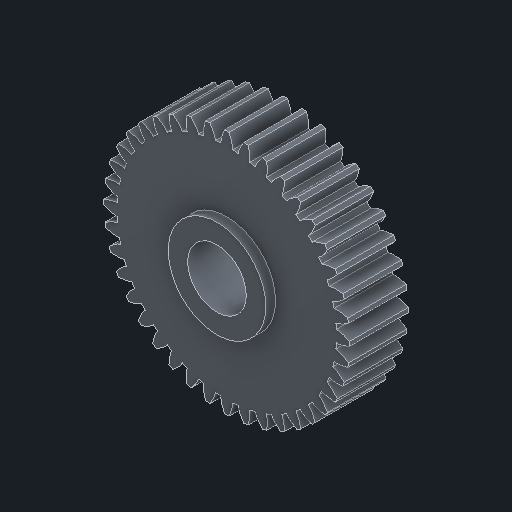
# Autodesk Inventor part: G2
Saved by Autodesk Inventor 2027 (Build 310192000, 192)
## iProperties
Created: 2026-11-10
Part Number: G2
Material: Genérico
Description: Engrenagem G2
Document SubType Name: Modeling
Designer: Bruno Madela
Mass: 40.9588 g
Surface Area: 123.761 cm^2
Volume: 40.9588 cm^3
Density: 1 g/cm^3
Appearance: Aço
Author: Bruno Madela
Autodesk Inventor part; units mm, degrees
(part 1 of 2)
ref_plane "YZ Plane" through (0, 0, 0) normal (1, 0, 0) x (0, 1, 0)
ref_plane "XZ Plane" through (0, 0, 0) normal (0, 1, 0) x (-1, 0, 0)
sketch "Esboço1" plane through (0, 0, 0) normal (0, 0, 1) x (1, 0, 0)
  circle A0 centre (0, 0) radius 12.5
  dimension "d0" = 25
  constraints: 1 centre point
  measures "d0" diameter of A0
extrude "Extrusão1" add sketch "Esboço1" along normal blind 20
ref_plane "Plano de trabalho1" through (0, 0, 2.5) normal (0, 0, 1) x (1, 0, 0)
sketch "Esboço2" plane through (0, 0, 2.5) normal (0, 0, 1) x (1, 0, 0)
  spline S0 degree 4 poles (28.0837, -1.5229) (28.1193, -1.5226) (28.1898, -1.5213) (28.2932, -1.5177) (28.4266, -1.5092) (28.5556, -1.4973) (28.6808, -1.4819) (28.8029, -1.4634) (28.9231, -1.4421) (29.0426, -1.4185) (29.1623, -1.3927) (29.2827, -1.3651) (29.4038, -1.3357) (29.525, -1.3045) (29.6461, -1.2716) (29.7667, -1.237) (29.887, -1.2007) (30.0069, -1.1627) (30.1267, -1.1233) (30.2466, -1.0824) (30.3664, -1.04) (30.486, -0.9963) (30.6056, -0.9511) (30.7248, -0.9046) (30.8438, -0.8568) (30.9626, -0.8076) (31.0812, -0.7571) (31.1996, -0.7054) (31.3178, -0.6525) (31.4064, -0.6118) (31.4654, -0.5843) (31.4948, -0.5705) knots 0 0 0 0 0 0.035714 0.071429 0.107143 0.142857 0.178571 0.214286 0.25 0.285714 0.321429 0.357143 0.392857 0.428571 0.464286 0.5 0.535714 0.571429 0.607143 0.642857 0.678571 0.714286 0.75 0.785714 0.821429 0.857143 0.892857 0.928571 0.964286 1 1 1 1 1
  spline S1 degree 4 poles (31.4948, 0.5705) (31.4653, 0.5845) (31.4062, 0.6123) (31.3175, 0.6534) (31.1991, 0.707) (31.0805, 0.7593) (30.9617, 0.8102) (30.8428, 0.8599) (30.7236, 0.9082) (30.6042, 0.9551) (30.4846, 1.0006) (30.3648, 1.0447) (30.2449, 1.0873) (30.125, 1.1284) (30.0051, 1.1681) (29.8851, 1.2062) (29.7648, 1.2427) (29.6441, 1.2774) (29.523, 1.3103) (29.4018, 1.3414) (29.2807, 1.3707) (29.1602, 1.3983) (29.0405, 1.424) (28.9209, 1.4477) (28.8007, 1.4688) (28.6787, 1.487) (28.5537, 1.5019) (28.425, 1.513) (28.2921, 1.5202) (28.1892, 1.5227) (28.1191, 1.5231) (28.0837, 1.5229) knots 0 0 0 0 0 0.035714 0.071429 0.107143 0.142857 0.178571 0.214286 0.25 0.285714 0.321429 0.357143 0.392857 0.428571 0.464286 0.5 0.535714 0.571429 0.607143 0.642857 0.678571 0.714286 0.75 0.785714 0.821429 0.857143 0.892857 0.928571 0.964286 1 1 1 1 1
  spline S2 degree 4 poles (27.9762, 2.8891) (28.0112, 2.8945) (28.0802, 2.9059) (28.1813, 2.9245) (28.3113, 2.9526) (28.4365, 2.9838) (28.5575, 3.0181) (28.6751, 3.0553) (28.7905, 3.0951) (28.9048, 3.1372) (29.019, 3.1815) (29.1336, 3.2276) (29.2486, 3.2756) (29.3635, 3.3253) (29.4779, 3.3767) (29.5917, 3.4299) (29.7048, 3.4847) (29.8174, 3.5411) (29.9296, 3.599) (30.0417, 3.6583) (30.1535, 3.7191) (30.265, 3.7813) (30.3761, 3.8449) (30.4867, 3.9099) (30.597, 3.9761) (30.7068, 4.0437) (30.8162, 4.1125) (30.9253, 4.1826) (31.034, 4.2539) (31.1152, 4.3083) (31.1693, 4.345) (31.1963, 4.3634) knots 0 0 0 0 0 0.035714 0.071429 0.107143 0.142857 0.178571 0.214286 0.25 0.285714 0.321429 0.357143 0.392857 0.428571 0.464286 0.5 0.535714 0.571429 0.607143 0.642857 0.678571 0.714286 0.75 0.785714 0.821429 0.857143 0.892857 0.928571 0.964286 1 1 1 1 1
  spline S3 degree 4 poles (31.0178, 5.4903) (30.9865, 5.4996) (30.9238, 5.5178) (30.8297, 5.5446) (30.7044, 5.579) (30.5791, 5.6121) (30.4538, 5.6439) (30.3285, 5.6743) (30.2033, 5.7034) (30.078, 5.7311) (29.9527, 5.7573) (29.8275, 5.7821) (29.7024, 5.8055) (29.5775, 5.8274) (29.4529, 5.8478) (29.3284, 5.8667) (29.2039, 5.8839) (29.0793, 5.8993) (28.9545, 5.9128) (28.8299, 5.9246) (28.7057, 5.9346) (28.5824, 5.943) (28.4601, 5.9497) (28.3383, 5.9543) (28.2163, 5.9564) (28.0929, 5.9553) (27.9672, 5.9503) (27.8383, 5.9411) (27.706, 5.9275) (27.6039, 5.9138) (27.5347, 5.9031) (27.4997, 5.8974) knots 0 0 0 0 0 0.035714 0.071429 0.107143 0.142857 0.178571 0.214286 0.25 0.285714 0.321429 0.357143 0.392857 0.428571 0.464286 0.5 0.535714 0.571429 0.607143 0.642857 0.678571 0.714286 0.75 0.785714 0.821429 0.857143 0.892857 0.928571 0.964286 1 1 1 1 1
  spline S4 degree 4 poles (27.1798, 7.23) (27.2135, 7.2408) (27.28, 7.2627) (27.377, 7.2969) (27.5011, 7.3448) (27.6199, 7.3952) (27.7341, 7.4479) (27.8445, 7.503) (27.9523, 7.5603) (28.0586, 7.6197) (28.1645, 7.6813) (28.2705, 7.7447) (28.3766, 7.8101) (28.4823, 7.8771) (28.5873, 7.9459) (28.6913, 8.0162) (28.7945, 8.088) (28.8968, 8.1613) (28.9986, 8.2361) (29.1, 8.3123) (29.2009, 8.3899) (29.3012, 8.4688) (29.401, 8.549) (29.5001, 8.6305) (29.5986, 8.7132) (29.6964, 8.7972) (29.7937, 8.8824) (29.8904, 8.9687) (29.9865, 9.0562) (30.0582, 9.1227) (30.1059, 9.1674) (30.1297, 9.1899) knots 0 0 0 0 0 0.035714 0.071429 0.107143 0.142857 0.178571 0.214286 0.25 0.285714 0.321429 0.357143 0.392857 0.428571 0.464286 0.5 0.535714 0.571429 0.607143 0.642857 0.678571 0.714286 0.75 0.785714 0.821429 0.857143 0.892857 0.928571 0.964286 1 1 1 1 1
  spline S5 degree 4 poles (29.7771, 10.275) (29.7447, 10.2792) (29.6799, 10.2874) (29.5829, 10.2991) (29.4537, 10.3135) (29.3248, 10.3266) (29.1961, 10.3383) (29.0677, 10.3488) (28.9394, 10.3579) (28.8114, 10.3657) (28.6836, 10.372) (28.556, 10.3769) (28.4289, 10.3804) (28.3021, 10.3825) (28.1758, 10.3831) (28.0499, 10.3823) (27.9243, 10.3798) (27.7988, 10.3755) (27.6734, 10.3694) (27.5485, 10.3615) (27.4243, 10.352) (27.3012, 10.341) (27.1794, 10.3284) (27.0584, 10.3139) (26.9376, 10.2969) (26.8159, 10.2764) (26.6925, 10.2519) (26.5666, 10.2227) (26.4379, 10.1885) (26.3391, 10.1591) (26.2723, 10.1378) (26.2386, 10.1267) knots 0 0 0 0 0 0.035714 0.071429 0.107143 0.142857 0.178571 0.214286 0.25 0.285714 0.321429 0.357143 0.392857 0.428571 0.464286 0.5 0.535714 0.571429 0.607143 0.642857 0.678571 0.714286 0.75 0.785714 0.821429 0.857143 0.892857 0.928571 0.964286 1 1 1 1 1
  spline S6 degree 4 poles (25.7142, 11.3928) (25.7458, 11.4088) (25.808, 11.4409) (25.8984, 11.4898) (26.0134, 11.5566) (26.1229, 11.625) (26.2274, 11.695) (26.3278, 11.7667) (26.4252, 11.8402) (26.521, 11.9156) (26.616, 11.9929) (26.7107, 12.0722) (26.8053, 12.1533) (26.8992, 12.2361) (26.9921, 12.3204) (27.0839, 12.4061) (27.1745, 12.4932) (27.2642, 12.5817) (27.353, 12.6714) (27.4412, 12.7625) (27.5287, 12.8549) (27.6155, 12.9485) (27.7015, 13.0433) (27.7867, 13.1393) (27.871, 13.2364) (27.9545, 13.3346) (28.0373, 13.4339) (28.1193, 13.5343) (28.2006, 13.6357) (28.2611, 13.7126) (28.3011, 13.7642) (28.3211, 13.7901) knots 0 0 0 0 0 0.035714 0.071429 0.107143 0.142857 0.178571 0.214286 0.25 0.285714 0.321429 0.357143 0.392857 0.428571 0.464286 0.5 0.535714 0.571429 0.607143 0.642857 0.678571 0.714286 0.75 0.785714 0.821429 0.857143 0.892857 0.928571 0.964286 1 1 1 1 1
  spline S7 degree 4 poles (27.8031, 14.8066) (27.7704, 14.8057) (27.7052, 14.8037) (27.6075, 14.8001) (27.4776, 14.7941) (27.3482, 14.7868) (27.2193, 14.7783) (27.0907, 14.7685) (26.9626, 14.7575) (26.8349, 14.7451) (26.7077, 14.7313) (26.581, 14.7162) (26.4548, 14.6998) (26.3293, 14.682) (26.2044, 14.6629) (26.0802, 14.6424) (25.9565, 14.6202) (25.8332, 14.5964) (25.7104, 14.5707) (25.5882, 14.5434) (25.467, 14.5146) (25.3471, 14.4845) (25.2287, 14.453) (25.1115, 14.4198) (24.9947, 14.3841) (24.8777, 14.3449) (24.7596, 14.3013) (24.6399, 14.2528) (24.5183, 14.1989) (24.4255, 14.1544) (24.3629, 14.1229) (24.3314, 14.1067) knots 0 0 0 0 0 0.035714 0.071429 0.107143 0.142857 0.178571 0.214286 0.25 0.285714 0.321429 0.357143 0.392857 0.428571 0.464286 0.5 0.535714 0.571429 0.607143 0.642857 0.678571 0.714286 0.75 0.785714 0.821429 0.857143 0.892857 0.928571 0.964286 1 1 1 1 1
  spline S8 degree 4 poles (23.6154, 15.2751) (23.6441, 15.2958) (23.7005, 15.3372) (23.7823, 15.3997) (23.8855, 15.4836) (23.983, 15.5682) (24.0754, 15.6536) (24.1634, 15.7401) (24.2482, 15.8279) (24.331, 15.9173) (24.4127, 16.0086) (24.4939, 16.1017) (24.5746, 16.1966) (24.6545, 16.2931) (24.7331, 16.3909) (24.8103, 16.4899) (24.8862, 16.5901) (24.9609, 16.6914) (25.0346, 16.794) (25.1074, 16.8978) (25.1794, 17.0027) (25.2504, 17.1088) (25.3205, 17.2159) (25.3895, 17.3241) (25.4576, 17.4332) (25.5246, 17.5433) (25.5908, 17.6544) (25.6561, 17.7664) (25.7204, 17.8793) (25.7681, 17.9647) (25.7995, 18.022) (25.8152, 18.0507) knots 0 0 0 0 0 0.035714 0.071429 0.107143 0.142857 0.178571 0.214286 0.25 0.285714 0.321429 0.357143 0.392857 0.428571 0.464286 0.5 0.535714 0.571429 0.607143 0.642857 0.678571 0.714286 0.75 0.785714 0.821429 0.857143 0.892857 0.928571 0.964286 1 1 1 1 1
  spline S9 degree 4 poles (25.1445, 18.9737) (25.1124, 18.9677) (25.0483, 18.9555) (24.9524, 18.9366) (24.8252, 18.9102) (24.6986, 18.8828) (24.5726, 18.8542) (24.4472, 18.8244) (24.3224, 18.7934) (24.1983, 18.7611) (24.0748, 18.7276) (23.952, 18.6928) (23.83, 18.6568) (23.7088, 18.6196) (23.5885, 18.5812) (23.4691, 18.5414) (23.3503, 18.5002) (23.2323, 18.4574) (23.115, 18.4128) (22.9986, 18.3667) (22.8834, 18.3193) (22.7697, 18.2708) (22.6577, 18.2212) (22.547, 18.1701) (22.4373, 18.1166) (22.3278, 18.0596) (22.218, 17.9982) (22.1072, 17.9316) (21.9954, 17.8594) (21.9106, 17.801) (21.8537, 17.7602) (21.8251, 17.7393) knots 0 0 0 0 0 0.035714 0.071429 0.107143 0.142857 0.178571 0.214286 0.25 0.285714 0.321429 0.357143 0.392857 0.428571 0.464286 0.5 0.535714 0.571429 0.607143 0.642857 0.678571 0.714286 0.75 0.785714 0.821429 0.857143 0.892857 0.928571 0.964286 1 1 1 1 1
  spline S10 degree 4 poles (20.9351, 18.7813) (20.9601, 18.8063) (21.0093, 18.856) (21.0802, 18.9305) (21.1688, 19.0296) (21.2517, 19.1285) (21.3295, 19.2273) (21.4027, 19.3265) (21.4726, 19.4265) (21.5403, 19.5278) (21.6067, 19.6307) (21.6723, 19.7354) (21.7371, 19.8418) (21.8009, 19.9495) (21.8632, 20.0584) (21.924, 20.1683) (21.9833, 20.2791) (22.0412, 20.3909) (22.098, 20.5038) (22.1538, 20.6177) (22.2085, 20.7326) (22.2621, 20.8484) (22.3147, 20.9652) (22.366, 21.0828) (22.4163, 21.2012) (22.4654, 21.3204) (22.5135, 21.4404) (22.5606, 21.5612) (22.6066, 21.6828) (22.6404, 21.7746) (22.6626, 21.836) (22.6736, 21.8668) knots 0 0 0 0 0 0.035714 0.071429 0.107143 0.142857 0.178571 0.214286 0.25 0.285714 0.321429 0.357143 0.392857 0.428571 0.464286 0.5 0.535714 0.571429 0.607143 0.642857 0.678571 0.714286 0.75 0.785714 0.821429 0.857143 0.892857 0.928571 0.964286 1 1 1 1 1
  spline S11 degree 4 poles (21.8668, 22.6736) (21.836, 22.6626) (21.7745, 22.6405) (21.6827, 22.6069) (21.5611, 22.5611) (21.4403, 22.5142) (21.3202, 22.4662) (21.201, 22.4173) (21.0825, 22.3672) (20.9649, 22.3159) (20.8482, 22.2635) (20.7323, 22.21) (20.6174, 22.1553) (20.5035, 22.0997) (20.3906, 22.0429) (20.2788, 21.985) (20.168, 21.9257) (20.0581, 21.865) (19.9492, 21.8026) (19.8414, 21.7388) (19.7351, 21.674) (19.6304, 21.6083) (19.5275, 21.5418) (19.4262, 21.474) (19.3263, 21.4039) (19.2271, 21.3305) (19.1283, 21.2526) (19.0295, 21.1694) (18.9304, 21.0806) (18.856, 21.0095) (18.8062, 20.9602) (18.7813, 20.9351) knots 0 0 0 0 0 0.035714 0.071429 0.107143 0.142857 0.178571 0.214286 0.25 0.285714 0.321429 0.357143 0.392857 0.428571 0.464286 0.5 0.535714 0.571429 0.607143 0.642857 0.678571 0.714286 0.75 0.785714 0.821429 0.857143 0.892857 0.928571 0.964286 1 1 1 1 1
  spline S12 degree 4 poles (17.7393, 21.8251) (17.7602, 21.8536) (17.801, 21.9105) (17.8595, 21.9952) (17.9316, 22.1069) (17.9982, 22.2175) (18.0596, 22.3274) (18.1165, 22.4368) (18.17, 22.5465) (18.2211, 22.6572) (18.2707, 22.7692) (18.3191, 22.8829) (18.3665, 22.9981) (18.4126, 23.1145) (18.4572, 23.2318) (18.5, 23.3498) (18.5413, 23.4686) (18.581, 23.5881) (18.6194, 23.7084) (18.6566, 23.8296) (18.6926, 23.9516) (18.7274, 24.0744) (18.761, 24.1979) (18.7932, 24.3221) (18.8243, 24.4469) (18.8541, 24.5723) (18.8827, 24.6984) (18.9102, 24.825) (18.9365, 24.9523) (18.9554, 25.0482) (18.9677, 25.1124) (18.9737, 25.1445) knots 0 0 0 0 0 0.035714 0.071429 0.107143 0.142857 0.178571 0.214286 0.25 0.285714 0.321429 0.357143 0.392857 0.428571 0.464286 0.5 0.535714 0.571429 0.607143 0.642857 0.678571 0.714286 0.75 0.785714 0.821429 0.857143 0.892857 0.928571 0.964286 1 1 1 1 1
  spline S13 degree 4 poles (18.0507, 25.8152) (18.022, 25.7995) (17.9647, 25.7681) (17.8793, 25.7205) (17.7664, 25.6562) (17.6544, 25.591) (17.5434, 25.5249) (17.4333, 25.4578) (17.3242, 25.3898) (17.216, 25.3208) (17.1089, 25.2508) (17.0029, 25.1798) (16.8979, 25.1078) (16.7942, 25.035) (16.6916, 24.9613) (16.5902, 24.8866) (16.49, 24.8107) (16.391, 24.7335) (16.2932, 24.6549) (16.1968, 24.5751) (16.1019, 24.4944) (16.0087, 24.4131) (15.9175, 24.3313) (15.8281, 24.2485) (15.7403, 24.1637) (15.6538, 24.0756) (15.5684, 23.9832) (15.4837, 23.8856) (15.3998, 23.7824) (15.3373, 23.7006) (15.2958, 23.6441) (15.2751, 23.6154) knots 0 0 0 0 0 0.035714 0.071429 0.107143 0.142857 0.178571 0.214286 0.25 0.285714 0.321429 0.357143 0.392857 0.428571 0.464286 0.5 0.535714 0.571429 0.607143 0.642857 0.678571 0.714286 0.75 0.785714 0.821429 0.857143 0.892857 0.928571 0.964286 1 1 1 1 1
  spline S14 degree 4 poles (14.1067, 24.3314) (14.1229, 24.3628) (14.1544, 24.4254) (14.199, 24.5181) (14.2529, 24.6397) (14.3014, 24.7594) (14.345, 24.8774) (14.3841, 24.9944) (14.4199, 25.1111) (14.453, 25.2284) (14.4845, 25.3468) (14.5146, 25.4667) (14.5434, 25.5879) (14.5708, 25.71) (14.5964, 25.8329) (14.6203, 25.9562) (14.6424, 26.0799) (14.6629, 26.2041) (14.682, 26.329) (14.6998, 26.4545) (14.7162, 26.5807) (14.7313, 26.7075) (14.7451, 26.8347) (14.7575, 26.9624) (14.7686, 27.0906) (14.7783, 27.2191) (14.7868, 27.3481) (14.7941, 27.4775) (14.8001, 27.6074) (14.8037, 27.7051) (14.8057, 27.7704) (14.8066, 27.8031) knots 0 0 0 0 0 0.035714 0.071429 0.107143 0.142857 0.178571 0.214286 0.25 0.285714 0.321429 0.357143 0.392857 0.428571 0.464286 0.5 0.535714 0.571429 0.607143 0.642857 0.678571 0.714286 0.75 0.785714 0.821429 0.857143 0.892857 0.928571 0.964286 1 1 1 1 1
  spline S15 degree 4 poles (13.7901, 28.3211) (13.7642, 28.3011) (13.7126, 28.2611) (13.6357, 28.2008) (13.5342, 28.1196) (13.4338, 28.0377) (13.3345, 27.955) (13.2363, 27.8716) (13.1392, 27.7873) (13.0432, 27.7022) (12.9483, 27.6163) (12.8547, 27.5296) (12.7623, 27.4421) (12.6712, 27.354) (12.5814, 27.2651) (12.493, 27.1755) (12.4059, 27.0849) (12.3202, 26.9931) (12.2359, 26.9002) (12.1531, 26.8062) (12.072, 26.7117) (11.9928, 26.6169) (11.9154, 26.5218) (11.8401, 26.426) (11.7666, 26.3285) (11.695, 26.228) (11.625, 26.1233) (11.5567, 26.0137) (11.4899, 25.8986) (11.4409, 25.8081) (11.4088, 25.7458) (11.3928, 25.7142) knots 0 0 0 0 0 0.035714 0.071429 0.107143 0.142857 0.178571 0.214286 0.25 0.285714 0.321429 0.357143 0.392857 0.428571 0.464286 0.5 0.535714 0.571429 0.607143 0.642857 0.678571 0.714286 0.75 0.785714 0.821429 0.857143 0.892857 0.928571 0.964286 1 1 1 1 1
  spline S16 degree 4 poles (10.1267, 26.2386) (10.1378, 26.2722) (10.1592, 26.3389) (10.1887, 26.4375) (10.2228, 26.566) (10.2521, 26.6918) (10.2766, 26.8153) (10.297, 26.937) (10.314, 27.0578) (10.3284, 27.1788) (10.341, 27.3007) (10.352, 27.4238) (10.3615, 27.548) (10.3694, 27.673) (10.3755, 27.7983) (10.3798, 27.9238) (10.3822, 28.0495) (10.3831, 28.1754) (10.3824, 28.3017) (10.3803, 28.4285) (10.3768, 28.5557) (10.3719, 28.6832) (10.3656, 28.8111) (10.3579, 28.9391) (10.3488, 29.0674) (10.3383, 29.1959) (10.3265, 29.3246) (10.3135, 29.4536) (10.2991, 29.5828) (10.2874, 29.6799) (10.2792, 29.7447) (10.275, 29.7771) knots 0 0 0 0 0 0.035714 0.071429 0.107143 0.142857 0.178571 0.214286 0.25 0.285714 0.321429 0.357143 0.392857 0.428571 0.464286 0.5 0.535714 0.571429 0.607143 0.642857 0.678571 0.714286 0.75 0.785714 0.821429 0.857143 0.892857 0.928571 0.964286 1 1 1 1 1
  spline S17 degree 4 poles (9.1899, 30.1297) (9.1674, 30.1059) (9.1226, 30.0583) (9.0561, 29.9867) (8.9685, 29.8906) (8.8821, 29.794) (8.7968, 29.6968) (8.7128, 29.5991) (8.63, 29.5007) (8.5484, 29.4016) (8.4681, 29.3019) (8.3892, 29.2016) (8.3116, 29.1008) (8.2354, 28.9995) (8.1606, 28.8977) (8.0872, 28.7953) (8.0154, 28.6922) (7.945, 28.5881) (7.8763, 28.4832) (7.8093, 28.3774) (7.744, 28.2713) (7.6805, 28.1653) (7.619, 28.0593) (7.5596, 27.9529) (7.5024, 27.8451) (7.4474, 27.7346) (7.3947, 27.6203) (7.3445, 27.5013) (7.2967, 27.3772) (7.2626, 27.2801) (7.2407, 27.2135) (7.23, 27.1798) knots 0 0 0 0 0 0.035714 0.071429 0.107143 0.142857 0.178571 0.214286 0.25 0.285714 0.321429 0.357143 0.392857 0.428571 0.464286 0.5 0.535714 0.571429 0.607143 0.642857 0.678571 0.714286 0.75 0.785714 0.821429 0.857143 0.892857 0.928571 0.964286 1 1 1 1 1
  spline S18 degree 4 poles (5.8974, 27.4997) (5.9031, 27.5347) (5.9138, 27.6039) (5.9275, 27.7059) (5.9412, 27.8382) (5.9504, 27.967) (5.9553, 28.0927) (5.9565, 28.2161) (5.9544, 28.3382) (5.9497, 28.4599) (5.943, 28.5823) (5.9346, 28.7056) (5.9246, 28.8297) (5.9128, 28.9544) (5.8993, 29.0791) (5.8839, 29.2038) (5.8667, 29.3283) (5.8478, 29.4528) (5.8274, 29.5774) (5.8055, 29.7023) (5.7821, 29.8274) (5.7573, 29.9526) (5.7311, 30.0779) (5.7034, 30.2032) (5.6743, 30.3284) (5.6439, 30.4537) (5.6121, 30.579) (5.579, 30.7043) (5.5446, 30.8297) (5.5178, 30.9238) (5.4996, 30.9865) (5.4903, 31.0178) knots 0 0 0 0 0 0.035714 0.071429 0.107143 0.142857 0.178571 0.214286 0.25 0.285714 0.321429 0.357143 0.392857 0.428571 0.464286 0.5 0.535714 0.571429 0.607143 0.642857 0.678571 0.714286 0.75 0.785714 0.821429 0.857143 0.892857 0.928571 0.964286 1 1 1 1 1
  spline S19 degree 4 poles (4.3634, 31.1963) (4.3449, 31.1694) (4.3082, 31.1154) (4.2536, 31.0342) (4.1822, 30.9256) (4.112, 30.8167) (4.043, 30.7073) (3.9753, 30.5976) (3.9089, 30.4875) (3.8439, 30.3769) (3.7802, 30.2659) (3.7179, 30.1545) (3.657, 30.0427) (3.5976, 29.9307) (3.5396, 29.8185) (3.4832, 29.7059) (3.4284, 29.5928) (3.3752, 29.4791) (3.3238, 29.3646) (3.2741, 29.2497) (3.2262, 29.1347) (3.1801, 29.0201) (3.1359, 28.9058) (3.0939, 28.7914) (3.0542, 28.6759) (3.0172, 28.5582) (2.983, 28.4371) (2.952, 28.3117) (2.9241, 28.1816) (2.9057, 28.0804) (2.8945, 28.0112) (2.8891, 27.9762) knots 0 0 0 0 0 0.035714 0.071429 0.107143 0.142857 0.178571 0.214286 0.25 0.285714 0.321429 0.357143 0.392857 0.428571 0.464286 0.5 0.535714 0.571429 0.607143 0.642857 0.678571 0.714286 0.75 0.785714 0.821429 0.857143 0.892857 0.928571 0.964286 1 1 1 1 1
  spline S20 degree 4 poles (1.5229, 28.0837) (1.5231, 28.1191) (1.5229, 28.1892) (1.5205, 28.292) (1.5134, 28.4249) (1.5024, 28.5535) (1.4877, 28.6785) (1.4695, 28.8006) (1.4484, 28.9208) (1.4247, 29.0403) (1.399, 29.1601) (1.3715, 29.2806) (1.3421, 29.4017) (1.311, 29.523) (1.2781, 29.644) (1.2434, 29.7647) (1.2069, 29.885) (1.1688, 30.005) (1.1291, 30.1249) (1.0879, 30.2448) (1.0453, 30.3647) (1.0012, 30.4845) (0.9556, 30.6042) (0.9087, 30.7236) (0.8603, 30.8427) (0.8106, 30.9617) (0.7595, 31.0805) (0.7072, 31.1991) (0.6536, 31.3175) (0.6124, 31.4062) (0.5845, 31.4653) (0.5705, 31.4948) knots 0 0 0 0 0 0.035714 0.071429 0.107143 0.142857 0.178571 0.214286 0.25 0.285714 0.321429 0.357143 0.392857 0.428571 0.464286 0.5 0.535714 0.571429 0.607143 0.642857 0.678571 0.714286 0.75 0.785714 0.821429 0.857143 0.892857 0.928571 0.964286 1 1 1 1 1
  spline S21 degree 4 poles (-0.5705, 31.4948) (-0.5845, 31.4653) (-0.6124, 31.4062) (-0.6536, 31.3175) (-0.7072, 31.1991) (-0.7596, 31.0805) (-0.8106, 30.9617) (-0.8603, 30.8428) (-0.9087, 30.7236) (-0.9557, 30.6042) (-1.0012, 30.4846) (-1.0453, 30.3648) (-1.088, 30.2449) (-1.1292, 30.125) (-1.1689, 30.0051) (-1.207, 29.8851) (-1.2435, 29.7648) (-1.2782, 29.6441) (-1.3111, 29.523) (-1.3422, 29.4017) (-1.3715, 29.2807) (-1.3991, 29.1602) (-1.4248, 29.0404) (-1.4484, 28.9208) (-1.4695, 28.8006) (-1.4877, 28.6786) (-1.5024, 28.5536) (-1.5134, 28.4249) (-1.5205, 28.2921) (-1.5229, 28.1892) (-1.5231, 28.1191) (-1.5229, 28.0837) knots 0 0 0 0 0 0.035714 0.071429 0.107143 0.142857 0.178571 0.214286 0.25 0.285714 0.321429 0.357143 0.392857 0.428571 0.464286 0.5 0.535714 0.571429 0.607143 0.642857 0.678571 0.714286 0.75 0.785714 0.821429 0.857143 0.892857 0.928571 0.964286 1 1 1 1 1
  spline S22 degree 4 poles (-2.8891, 27.9762) (-2.8944, 28.0112) (-2.9056, 28.0803) (-2.924, 28.1816) (-2.9518, 28.3117) (-2.9828, 28.437) (-3.0169, 28.5582) (-3.0539, 28.6759) (-3.0936, 28.7913) (-3.1356, 28.9057) (-3.1798, 29.02) (-3.2258, 29.1347) (-3.2737, 29.2496) (-3.3234, 29.3646) (-3.3749, 29.479) (-3.4281, 29.5928) (-3.4829, 29.7059) (-3.5393, 29.8184) (-3.5973, 29.9307) (-3.6567, 30.0427) (-3.7176, 30.1544) (-3.7799, 30.2658) (-3.8436, 30.3769) (-3.9087, 30.4875) (-3.9751, 30.5976) (-4.0428, 30.7073) (-4.1118, 30.8166) (-4.1821, 30.9256) (-4.2536, 31.0342) (-4.3082, 31.1154) (-4.3449, 31.1694) (-4.3634, 31.1963) knots 0 0 0 0 0 0.035714 0.071429 0.107143 0.142857 0.178571 0.214286 0.25 0.285714 0.321429 0.357143 0.392857 0.428571 0.464286 0.5 0.535714 0.571429 0.607143 0.642857 0.678571 0.714286 0.75 0.785714 0.821429 0.857143 0.892857 0.928571 0.964286 1 1 1 1 1
  spline S23 degree 4 poles (-5.4903, 31.0178) (-5.4996, 30.9865) (-5.5179, 30.9238) (-5.5447, 30.8297) (-5.5791, 30.7043) (-5.6122, 30.579) (-5.644, 30.4537) (-5.6745, 30.3285) (-5.7036, 30.2032) (-5.7313, 30.0779) (-5.7576, 29.9526) (-5.7824, 29.8274) (-5.8058, 29.7023) (-5.8277, 29.5775) (-5.8482, 29.4528) (-5.867, 29.3283) (-5.8842, 29.2038) (-5.8997, 29.0792) (-5.9132, 28.9544) (-5.925, 28.8298) (-5.935, 28.7056) (-5.9434, 28.5823) (-5.95, 28.46) (-5.9547, 28.3382) (-5.9567, 28.2161) (-5.9556, 28.0927) (-5.9506, 27.967) (-5.9414, 27.8382) (-5.9276, 27.7059) (-5.9139, 27.6039) (-5.9032, 27.5347) (-5.8974, 27.4997) knots 0 0 0 0 0 0.035714 0.071429 0.107143 0.142857 0.178571 0.214286 0.25 0.285714 0.321429 0.357143 0.392857 0.428571 0.464286 0.5 0.535714 0.571429 0.607143 0.642857 0.678571 0.714286 0.75 0.785714 0.821429 0.857143 0.892857 0.928571 0.964286 1 1 1 1 1
  spline S24 degree 4 poles (-7.23, 27.1798) (-7.2407, 27.2135) (-7.2626, 27.2801) (-7.2966, 27.3772) (-7.3444, 27.5013) (-7.3946, 27.6203) (-7.4472, 27.7346) (-7.5022, 27.8451) (-7.5595, 27.9529) (-7.6189, 28.0593) (-7.6804, 28.1652) (-7.7438, 28.2713) (-7.8091, 28.3774) (-7.8762, 28.4831) (-7.9449, 28.5881) (-8.0152, 28.6921) (-8.0871, 28.7953) (-8.1604, 28.8976) (-8.2352, 28.9994) (-8.3114, 29.1007) (-8.3891, 29.2016) (-8.468, 29.3019) (-8.5483, 29.4016) (-8.6299, 29.5006) (-8.7127, 29.599) (-8.7968, 29.6968) (-8.882, 29.794) (-8.9684, 29.8906) (-9.056, 29.9867) (-9.1226, 30.0583) (-9.1674, 30.1059) (-9.1899, 30.1297) knots 0 0 0 0 0 0.035714 0.071429 0.107143 0.142857 0.178571 0.214286 0.25 0.285714 0.321429 0.357143 0.392857 0.428571 0.464286 0.5 0.535714 0.571429 0.607143 0.642857 0.678571 0.714286 0.75 0.785714 0.821429 0.857143 0.892857 0.928571 0.964286 1 1 1 1 1
  spline S25 degree 4 poles (-10.275, 29.7771) (-10.2792, 29.7447) (-10.2875, 29.6798) (-10.2993, 29.5828) (-10.3137, 29.4535) (-10.3268, 29.3246) (-10.3387, 29.1959) (-10.3492, 29.0674) (-10.3584, 28.9391) (-10.3662, 28.811) (-10.3726, 28.6832) (-10.3775, 28.5556) (-10.381, 28.4284) (-10.3832, 28.3016) (-10.3839, 28.1753) (-10.383, 28.0494) (-10.3806, 27.9237) (-10.3763, 27.7982) (-10.3702, 27.6729) (-10.3623, 27.5479) (-10.3527, 27.4237) (-10.3417, 27.3006) (-10.3292, 27.1788) (-10.3147, 27.0577) (-10.2976, 26.9369) (-10.2771, 26.8152) (-10.2525, 26.6918) (-10.2232, 26.566) (-10.1889, 26.4375) (-10.1593, 26.3389) (-10.1379, 26.2722) (-10.1267, 26.2386) knots 0 0 0 0 0 0.035714 0.071429 0.107143 0.142857 0.178571 0.214286 0.25 0.285714 0.321429 0.357143 0.392857 0.428571 0.464286 0.5 0.535714 0.571429 0.607143 0.642857 0.678571 0.714286 0.75 0.785714 0.821429 0.857143 0.892857 0.928571 0.964286 1 1 1 1 1
  spline S26 degree 4 poles (-11.3928, 25.7142) (-11.4087, 25.7458) (-11.4407, 25.8081) (-11.4895, 25.8987) (-11.5561, 26.0138) (-11.6243, 26.1235) (-11.6941, 26.2282) (-11.7657, 26.3287) (-11.8391, 26.4262) (-11.9144, 26.522) (-11.9917, 26.6171) (-12.071, 26.7119) (-12.1521, 26.8064) (-12.2348, 26.9004) (-12.3191, 26.9933) (-12.4049, 27.0851) (-12.492, 27.1757) (-12.5804, 27.2653) (-12.6702, 27.3542) (-12.7614, 27.4423) (-12.8538, 27.5298) (-12.9475, 27.6165) (-13.0424, 27.7024) (-13.1385, 27.7875) (-13.2357, 27.8717) (-13.334, 27.9551) (-13.4334, 28.0377) (-13.5339, 28.1197) (-13.6355, 28.2008) (-13.7125, 28.2612) (-13.7641, 28.3012) (-13.7901, 28.3211) knots 0 0 0 0 0 0.035714 0.071429 0.107143 0.142857 0.178571 0.214286 0.25 0.285714 0.321429 0.357143 0.392857 0.428571 0.464286 0.5 0.535714 0.571429 0.607143 0.642857 0.678571 0.714286 0.75 0.785714 0.821429 0.857143 0.892857 0.928571 0.964286 1 1 1 1 1
  spline S27 degree 4 poles (-14.8066, 27.8031) (-14.8058, 27.7704) (-14.8038, 27.7051) (-14.8002, 27.6074) (-14.7943, 27.4775) (-14.7871, 27.3481) (-14.7787, 27.2191) (-14.769, 27.0905) (-14.758, 26.9624) (-14.7457, 26.8346) (-14.732, 26.7074) (-14.7169, 26.5806) (-14.7005, 26.4544) (-14.6828, 26.3289) (-14.6637, 26.204) (-14.6432, 26.0798) (-14.6211, 25.956) (-14.5972, 25.8327) (-14.5716, 25.7099) (-14.5442, 25.5877) (-14.5154, 25.4665) (-14.4852, 25.3467) (-14.4538, 25.2283) (-14.4205, 25.111) (-14.3847, 24.9943) (-14.3455, 24.8773) (-14.3018, 24.7593) (-14.2532, 24.6397) (-14.1992, 24.5181) (-14.1545, 24.4254) (-14.1229, 24.3628) (-14.1067, 24.3314) knots 0 0 0 0 0 0.035714 0.071429 0.107143 0.142857 0.178571 0.214286 0.25 0.285714 0.321429 0.357143 0.392857 0.428571 0.464286 0.5 0.535714 0.571429 0.607143 0.642857 0.678571 0.714286 0.75 0.785714 0.821429 0.857143 0.892857 0.928571 0.964286 1 1 1 1 1
  spline S28 degree 4 poles (-15.2751, 23.6154) (-15.2958, 23.6441) (-15.3371, 23.7007) (-15.3995, 23.7825) (-15.4833, 23.8858) (-15.5678, 23.9834) (-15.6532, 24.0759) (-15.7396, 24.164) (-15.8273, 24.2488) (-15.9167, 24.3316) (-16.0079, 24.4134) (-16.1011, 24.4947) (-16.1959, 24.5754) (-16.2924, 24.6552) (-16.3902, 24.7339) (-16.4892, 24.8111) (-16.5894, 24.887) (-16.6908, 24.9616) (-16.7934, 25.0353) (-16.8972, 25.1081) (-17.0022, 25.18) (-17.1083, 25.251) (-17.2155, 25.321) (-17.3237, 25.39) (-17.4328, 25.458) (-17.543, 25.525) (-17.6541, 25.5911) (-17.7662, 25.6563) (-17.8792, 25.7206) (-17.9647, 25.7681) (-18.022, 25.7995) (-18.0507, 25.8152) knots 0 0 0 0 0 0.035714 0.071429 0.107143 0.142857 0.178571 0.214286 0.25 0.285714 0.321429 0.357143 0.392857 0.428571 0.464286 0.5 0.535714 0.571429 0.607143 0.642857 0.678571 0.714286 0.75 0.785714 0.821429 0.857143 0.892857 0.928571 0.964286 1 1 1 1 1
  spline S29 degree 4 poles (-18.9737, 25.1445) (-18.9677, 25.1124) (-18.9556, 25.0482) (-18.9368, 24.9522) (-18.9106, 24.8249) (-18.8832, 24.6982) (-18.8547, 24.5721) (-18.8251, 24.4466) (-18.7942, 24.3218) (-18.762, 24.1976) (-18.7285, 24.074) (-18.6938, 23.9512) (-18.6579, 23.8291) (-18.6207, 23.7079) (-18.5824, 23.5875) (-18.5427, 23.468) (-18.5015, 23.3493) (-18.4586, 23.2312) (-18.4141, 23.1139) (-18.3679, 22.9975) (-18.3205, 22.8823) (-18.272, 22.7687) (-18.2224, 22.6566) (-18.1712, 22.546) (-18.1176, 22.4364) (-18.0605, 22.327) (-17.999, 22.2172) (-17.9322, 22.1066) (-17.8598, 21.995) (-17.8012, 21.9104) (-17.7602, 21.8536) (-17.7393, 21.8251) knots 0 0 0 0 0 0.035714 0.071429 0.107143 0.142857 0.178571 0.214286 0.25 0.285714 0.321429 0.357143 0.392857 0.428571 0.464286 0.5 0.535714 0.571429 0.607143 0.642857 0.678571 0.714286 0.75 0.785714 0.821429 0.857143 0.892857 0.928571 0.964286 1 1 1 1 1
  spline S30 degree 4 poles (-18.7813, 20.9351) (-18.8062, 20.9602) (-18.8559, 21.0096) (-18.9303, 21.0807) (-19.0292, 21.1696) (-19.128, 21.2528) (-19.2268, 21.3308) (-19.3259, 21.4042) (-19.4258, 21.4743) (-19.5271, 21.5422) (-19.63, 21.6087) (-19.7347, 21.6744) (-19.841, 21.7392) (-19.9487, 21.803) (-20.0576, 21.8654) (-20.1675, 21.9261) (-20.2784, 21.9854) (-20.3902, 22.0433) (-20.5031, 22.1) (-20.617, 22.1557) (-20.7319, 22.2103) (-20.8478, 22.2638) (-20.9646, 22.3162) (-21.0823, 22.3674) (-21.2007, 22.4175) (-21.32, 22.4664) (-21.4401, 22.5143) (-21.561, 22.5612) (-21.6827, 22.607) (-21.7745, 22.6406) (-21.836, 22.6626) (-21.8668, 22.6736) knots 0 0 0 0 0 0.035714 0.071429 0.107143 0.142857 0.178571 0.214286 0.25 0.285714 0.321429 0.357143 0.392857 0.428571 0.464286 0.5 0.535714 0.571429 0.607143 0.642857 0.678571 0.714286 0.75 0.785714 0.821429 0.857143 0.892857 0.928571 0.964286 1 1 1 1 1
  spline S31 degree 4 poles (-22.6736, 21.8668) (-22.6626, 21.836) (-22.6406, 21.7745) (-22.607, 21.6827) (-22.5612, 21.561) (-22.5144, 21.4401) (-22.4665, 21.32) (-22.4176, 21.2008) (-22.3675, 21.0823) (-22.3163, 20.9647) (-22.2639, 20.8479) (-22.2104, 20.732) (-22.1558, 20.617) (-22.1002, 20.5031) (-22.0434, 20.3903) (-21.9855, 20.2784) (-21.9263, 20.1676) (-21.8655, 20.0577) (-21.8031, 19.9488) (-21.7394, 19.8411) (-21.6745, 19.7347) (-21.6088, 19.63) (-21.5423, 19.5271) (-21.4744, 19.4259) (-21.4043, 19.326) (-21.3308, 19.2268) (-21.2529, 19.128) (-21.1696, 19.0293) (-21.0807, 18.9303) (-21.0096, 18.8559) (-20.9602, 18.8062) (-20.9351, 18.7813) knots 0 0 0 0 0 0.035714 0.071429 0.107143 0.142857 0.178571 0.214286 0.25 0.285714 0.321429 0.357143 0.392857 0.428571 0.464286 0.5 0.535714 0.571429 0.607143 0.642857 0.678571 0.714286 0.75 0.785714 0.821429 0.857143 0.892857 0.928571 0.964286 1 1 1 1 1
  spline S32 degree 4 poles (-21.8251, 17.7393) (-21.8536, 17.7602) (-21.9104, 17.8012) (-21.995, 17.8598) (-22.1066, 17.9321) (-22.2172, 17.9988) (-22.3269, 18.0603) (-22.4363, 18.1174) (-22.546, 18.1709) (-22.6566, 18.2221) (-22.7687, 18.2717) (-22.8823, 18.3202) (-22.9975, 18.3676) (-23.1139, 18.4137) (-23.2312, 18.4583) (-23.3492, 18.5011) (-23.468, 18.5423) (-23.5875, 18.582) (-23.7078, 18.6204) (-23.8291, 18.6575) (-23.9511, 18.6935) (-24.074, 18.7283) (-24.1975, 18.7617) (-24.3217, 18.7939) (-24.4466, 18.8249) (-24.5721, 18.8546) (-24.6982, 18.8831) (-24.8249, 18.9105) (-24.9522, 18.9367) (-25.0482, 18.9555) (-25.1124, 18.9677) (-25.1445, 18.9737) knots 0 0 0 0 0 0.035714 0.071429 0.107143 0.142857 0.178571 0.214286 0.25 0.285714 0.321429 0.357143 0.392857 0.428571 0.464286 0.5 0.535714 0.571429 0.607143 0.642857 0.678571 0.714286 0.75 0.785714 0.821429 0.857143 0.892857 0.928571 0.964286 1 1 1 1 1
  spline S33 degree 4 poles (-25.8152, 18.0507) (-25.7995, 18.022) (-25.7681, 17.9647) (-25.7206, 17.8792) (-25.6563, 17.7662) (-25.5912, 17.6541) (-25.5251, 17.543) (-25.4581, 17.4329) (-25.3901, 17.3237) (-25.3211, 17.2155) (-25.2511, 17.1084) (-25.1801, 17.0023) (-25.1082, 16.8973) (-25.0354, 16.7935) (-24.9618, 16.6909) (-24.8871, 16.5895) (-24.8112, 16.4893) (-24.734, 16.3903) (-24.6554, 16.2925) (-24.5755, 16.196) (-24.4948, 16.1011) (-24.4135, 16.008) (-24.3317, 15.9168) (-24.2489, 15.8274) (-24.164, 15.7397) (-24.0759, 15.6532) (-23.9835, 15.5679) (-23.8858, 15.4833) (-23.7825, 15.3995) (-23.7007, 15.3371) (-23.6441, 15.2958) (-23.6154, 15.2751) knots 0 0 0 0 0 0.035714 0.071429 0.107143 0.142857 0.178571 0.214286 0.25 0.285714 0.321429 0.357143 0.392857 0.428571 0.464286 0.5 0.535714 0.571429 0.607143 0.642857 0.678571 0.714286 0.75 0.785714 0.821429 0.857143 0.892857 0.928571 0.964286 1 1 1 1 1
  spline S34 degree 4 poles (-24.3314, 14.1067) (-24.3628, 14.1229) (-24.4253, 14.1545) (-24.5181, 14.1991) (-24.6396, 14.2531) (-24.7593, 14.3017) (-24.8773, 14.3453) (-24.9943, 14.3845) (-25.111, 14.4203) (-25.2282, 14.4535) (-25.3467, 14.4849) (-25.4665, 14.5151) (-25.5877, 14.5439) (-25.7099, 14.5713) (-25.8327, 14.5969) (-25.956, 14.6207) (-26.0797, 14.6429) (-26.204, 14.6634) (-26.3288, 14.6825) (-26.4544, 14.7002) (-26.5806, 14.7166) (-26.7073, 14.7317) (-26.8346, 14.7454) (-26.9623, 14.7578) (-27.0905, 14.7688) (-27.219, 14.7785) (-27.348, 14.787) (-27.4775, 14.7942) (-27.6074, 14.8002) (-27.7051, 14.8038) (-27.7704, 14.8058) (-27.8031, 14.8066) knots 0 0 0 0 0 0.035714 0.071429 0.107143 0.142857 0.178571 0.214286 0.25 0.285714 0.321429 0.357143 0.392857 0.428571 0.464286 0.5 0.535714 0.571429 0.607143 0.642857 0.678571 0.714286 0.75 0.785714 0.821429 0.857143 0.892857 0.928571 0.964286 1 1 1 1 1
  spline S35 degree 4 poles (-28.3211, 13.7901) (-28.3012, 13.7641) (-28.2612, 13.7125) (-28.2008, 13.6355) (-28.1197, 13.534) (-28.0378, 13.4335) (-27.9551, 13.3341) (-27.8717, 13.2358) (-27.7875, 13.1387) (-27.7024, 13.0426) (-27.6165, 12.9477) (-27.5298, 12.854) (-27.4424, 12.7616) (-27.3542, 12.6705) (-27.2654, 12.5807) (-27.1758, 12.4922) (-27.0852, 12.4051) (-26.9934, 12.3194) (-26.9004, 12.2351) (-26.8065, 12.1523) (-26.7119, 12.0712) (-26.6171, 11.992) (-26.522, 11.9147) (-26.4262, 11.8394) (-26.3287, 11.7659) (-26.2282, 11.6944) (-26.1235, 11.6245) (-26.0138, 11.5562) (-25.8987, 11.4896) (-25.8081, 11.4407) (-25.7458, 11.4087) (-25.7142, 11.3928) knots 0 0 0 0 0 0.035714 0.071429 0.107143 0.142857 0.178571 0.214286 0.25 0.285714 0.321429 0.357143 0.392857 0.428571 0.464286 0.5 0.535714 0.571429 0.607143 0.642857 0.678571 0.714286 0.75 0.785714 0.821429 0.857143 0.892857 0.928571 0.964286 1 1 1 1 1
  spline S36 degree 4 poles (-26.2386, 10.1267) (-26.2722, 10.1379) (-26.3389, 10.1593) (-26.4374, 10.1888) (-26.566, 10.223) (-26.6918, 10.2523) (-26.8152, 10.2769) (-26.9368, 10.2973) (-27.0577, 10.3144) (-27.1787, 10.3288) (-27.3006, 10.3414) (-27.4237, 10.3524) (-27.5479, 10.3619) (-27.6728, 10.3698) (-27.7982, 10.3759) (-27.9237, 10.3802) (-28.0493, 10.3827) (-28.1753, 10.3835) (-28.3016, 10.3828) (-28.4284, 10.3807) (-28.5556, 10.3772) (-28.6831, 10.3723) (-28.811, 10.3659) (-28.939, 10.3582) (-29.0673, 10.349) (-29.1958, 10.3385) (-29.3246, 10.3267) (-29.4535, 10.3136) (-29.5827, 10.2992) (-29.6798, 10.2875) (-29.7447, 10.2792) (-29.7771, 10.275) knots 0 0 0 0 0 0.035714 0.071429 0.107143 0.142857 0.178571 0.214286 0.25 0.285714 0.321429 0.357143 0.392857 0.428571 0.464286 0.5 0.535714 0.571429 0.607143 0.642857 0.678571 0.714286 0.75 0.785714 0.821429 0.857143 0.892857 0.928571 0.964286 1 1 1 1 1
  spline S37 degree 4 poles (-30.1297, 9.1899) (-30.1059, 9.1674) (-30.0583, 9.1227) (-29.9866, 9.0562) (-29.8905, 8.9686) (-29.7939, 8.8823) (-29.6967, 8.7971) (-29.5989, 8.7131) (-29.5005, 8.6303) (-29.4014, 8.5488) (-29.3017, 8.4686) (-29.2014, 8.3896) (-29.1005, 8.3121) (-28.9992, 8.2359) (-28.8974, 8.1611) (-28.7951, 8.0878) (-28.6919, 8.0159) (-28.5879, 7.9456) (-28.4829, 7.8769) (-28.3772, 7.8098) (-28.2711, 7.7445) (-28.1651, 7.6811) (-28.0591, 7.6195) (-27.9527, 7.5601) (-27.8449, 7.5028) (-27.7345, 7.4478) (-27.6202, 7.3951) (-27.5012, 7.3448) (-27.3771, 7.2968) (-27.2801, 7.2627) (-27.2135, 7.2408) (-27.1798, 7.23) knots 0 0 0 0 0 0.035714 0.071429 0.107143 0.142857 0.178571 0.214286 0.25 0.285714 0.321429 0.357143 0.392857 0.428571 0.464286 0.5 0.535714 0.571429 0.607143 0.642857 0.678571 0.714286 0.75 0.785714 0.821429 0.857143 0.892857 0.928571 0.964286 1 1 1 1 1
  spline S38 degree 4 poles (-27.4997, 5.8974) (-27.5347, 5.9032) (-27.6039, 5.9139) (-27.7059, 5.9276) (-27.8382, 5.9414) (-27.967, 5.9506) (-28.0927, 5.9556) (-28.2161, 5.9567) (-28.3382, 5.9547) (-28.4599, 5.95) (-28.5823, 5.9434) (-28.7056, 5.935) (-28.8297, 5.9249) (-28.9544, 5.9132) (-29.0791, 5.8996) (-29.2038, 5.8842) (-29.3283, 5.867) (-29.4528, 5.8481) (-29.5774, 5.8277) (-29.7023, 5.8058) (-29.8274, 5.7824) (-29.9526, 5.7576) (-30.0779, 5.7313) (-30.2032, 5.7036) (-30.3284, 5.6745) (-30.4537, 5.644) (-30.579, 5.6122) (-30.7043, 5.5791) (-30.8297, 5.5446) (-30.9238, 5.5179) (-30.9865, 5.4996) (-31.0178, 5.4903) knots 0 0 0 0 0 0.035714 0.071429 0.107143 0.142857 0.178571 0.214286 0.25 0.285714 0.321429 0.357143 0.392857 0.428571 0.464286 0.5 0.535714 0.571429 0.607143 0.642857 0.678571 0.714286 0.75 0.785714 0.821429 0.857143 0.892857 0.928571 0.964286 1 1 1 1 1
  spline S39 degree 4 poles (-31.1963, 4.3634) (-31.1694, 4.3449) (-31.1154, 4.3082) (-31.0342, 4.2536) (-30.9256, 4.1822) (-30.8167, 4.1119) (-30.7074, 4.043) (-30.5976, 3.9753) (-30.4875, 3.9089) (-30.3769, 3.8438) (-30.2659, 3.7801) (-30.1545, 3.7178) (-30.0427, 3.657) (-29.9307, 3.5975) (-29.8185, 3.5396) (-29.7059, 3.4831) (-29.5929, 3.4283) (-29.4791, 3.3751) (-29.3646, 3.3237) (-29.2497, 3.274) (-29.1347, 3.2261) (-29.0201, 3.18) (-28.9058, 3.1359) (-28.7914, 3.0938) (-28.6759, 3.0541) (-28.5582, 3.0171) (-28.4371, 2.983) (-28.3117, 2.952) (-28.1816, 2.9241) (-28.0804, 2.9057) (-28.0112, 2.8944) (-27.9762, 2.8891) knots 0 0 0 0 0 0.035714 0.071429 0.107143 0.142857 0.178571 0.214286 0.25 0.285714 0.321429 0.357143 0.392857 0.428571 0.464286 0.5 0.535714 0.571429 0.607143 0.642857 0.678571 0.714286 0.75 0.785714 0.821429 0.857143 0.892857 0.928571 0.964286 1 1 1 1 1
  spline S40 degree 4 poles (-28.0837, 1.5229) (-28.1191, 1.5231) (-28.1892, 1.5229) (-28.292, 1.5206) (-28.4249, 1.5135) (-28.5536, 1.5025) (-28.6785, 1.4878) (-28.8006, 1.4697) (-28.9208, 1.4485) (-29.0404, 1.4249) (-29.1602, 1.3992) (-29.2807, 1.3716) (-29.4017, 1.3423) (-29.523, 1.3112) (-29.6441, 1.2783) (-29.7648, 1.2436) (-29.885, 1.2071) (-30.0051, 1.169) (-30.125, 1.1293) (-30.2449, 1.0881) (-30.3648, 1.0454) (-30.4846, 1.0013) (-30.6042, 0.9558) (-30.7236, 0.9088) (-30.8428, 0.8604) (-30.9617, 0.8107) (-31.0805, 0.7596) (-31.1991, 0.7073) (-31.3175, 0.6536) (-31.4062, 0.6124) (-31.4653, 0.5845) (-31.4948, 0.5705) knots 0 0 0 0 0 0.035714 0.071429 0.107143 0.142857 0.178571 0.214286 0.25 0.285714 0.321429 0.357143 0.392857 0.428571 0.464286 0.5 0.535714 0.571429 0.607143 0.642857 0.678571 0.714286 0.75 0.785714 0.821429 0.857143 0.892857 0.928571 0.964286 1 1 1 1 1
  spline S41 degree 4 poles (-31.4948, -0.5705) (-31.4653, -0.5845) (-31.4062, -0.6123) (-31.3174, -0.6533) (-31.1989, -0.7068) (-31.0803, -0.759) (-30.9615, -0.8099) (-30.8425, -0.8595) (-30.7232, -0.9077) (-30.6038, -0.9546) (-30.4841, -1) (-30.3643, -1.044) (-30.2444, -1.0866) (-30.1245, -1.1277) (-30.0046, -1.1674) (-29.8845, -1.2055) (-29.7643, -1.2419) (-29.6436, -1.2766) (-29.5225, -1.3095) (-29.4012, -1.3407) (-29.2802, -1.37) (-29.1597, -1.3976) (-29.04, -1.4234) (-28.9204, -1.4471) (-28.8002, -1.4684) (-28.6782, -1.4867) (-28.5533, -1.5016) (-28.4247, -1.5128) (-28.2919, -1.5201) (-28.1891, -1.5227) (-28.1191, -1.523) (-28.0837, -1.5229) knots 0 0 0 0 0 0.035714 0.071429 0.107143 0.142857 0.178571 0.214286 0.25 0.285714 0.321429 0.357143 0.392857 0.428571 0.464286 0.5 0.535714 0.571429 0.607143 0.642857 0.678571 0.714286 0.75 0.785714 0.821429 0.857143 0.892857 0.928571 0.964286 1 1 1 1 1
  spline S42 degree 4 poles (-27.9762, -2.8891) (-28.0112, -2.8944) (-28.0803, -2.9057) (-28.1816, -2.9241) (-28.3117, -2.9519) (-28.437, -2.9829) (-28.5582, -3.0171) (-28.6759, -3.0541) (-28.7913, -3.0938) (-28.9057, -3.1358) (-29.02, -3.18) (-29.1347, -3.2261) (-29.2496, -3.274) (-29.3646, -3.3237) (-29.479, -3.3751) (-29.5928, -3.4283) (-29.7059, -3.4831) (-29.8184, -3.5395) (-29.9307, -3.5975) (-30.0427, -3.6569) (-30.1544, -3.7178) (-30.2658, -3.7801) (-30.3769, -3.8438) (-30.4874, -3.9088) (-30.5976, -3.9752) (-30.7073, -4.0429) (-30.8166, -4.1119) (-30.9256, -4.1821) (-31.0342, -4.2536) (-31.1153, -4.3082) (-31.1694, -4.3449) (-31.1963, -4.3634) knots 0 0 0 0 0 0.035714 0.071429 0.107143 0.142857 0.178571 0.214286 0.25 0.285714 0.321429 0.357143 0.392857 0.428571 0.464286 0.5 0.535714 0.571429 0.607143 0.642857 0.678571 0.714286 0.75 0.785714 0.821429 0.857143 0.892857 0.928571 0.964286 1 1 1 1 1
  spline S43 degree 4 poles (-31.0178, -5.4903) (-30.9865, -5.4996) (-30.9237, -5.5178) (-30.8297, -5.5446) (-30.7043, -5.579) (-30.579, -5.6121) (-30.4537, -5.6439) (-30.3284, -5.6743) (-30.2031, -5.7034) (-30.0778, -5.7311) (-29.9525, -5.7573) (-29.8273, -5.7821) (-29.7022, -5.8054) (-29.5773, -5.8273) (-29.4527, -5.8478) (-29.3282, -5.8666) (-29.2037, -5.8838) (-29.0791, -5.8993) (-28.9543, -5.9128) (-28.8297, -5.9246) (-28.7055, -5.9346) (-28.5822, -5.943) (-28.4599, -5.9497) (-28.3381, -5.9544) (-28.216, -5.9565) (-28.0927, -5.9553) (-27.9669, -5.9504) (-27.8381, -5.9412) (-27.7058, -5.9275) (-27.6039, -5.9138) (-27.5347, -5.9031) (-27.4997, -5.8974) knots 0 0 0 0 0 0.035714 0.071429 0.107143 0.142857 0.178571 0.214286 0.25 0.285714 0.321429 0.357143 0.392857 0.428571 0.464286 0.5 0.535714 0.571429 0.607143 0.642857 0.678571 0.714286 0.75 0.785714 0.821429 0.857143 0.892857 0.928571 0.964286 1 1 1 1 1
  spline S44 degree 4 poles (-27.1798, -7.23) (-27.2135, -7.2407) (-27.2801, -7.2626) (-27.3772, -7.2966) (-27.5013, -7.3444) (-27.6203, -7.3946) (-27.7346, -7.4472) (-27.8451, -7.5022) (-27.9529, -7.5594) (-28.0593, -7.6189) (-28.1653, -7.6803) (-28.2713, -7.7438) (-28.3774, -7.8091) (-28.4831, -7.8761) (-28.5881, -7.9449) (-28.6922, -8.0152) (-28.7953, -8.087) (-28.8977, -8.1604) (-28.9994, -8.2352) (-29.1008, -8.3114) (-29.2016, -8.389) (-29.3019, -8.468) (-29.4016, -8.5483) (-29.5007, -8.6299) (-29.5991, -8.7127) (-29.6968, -8.7967) (-29.794, -8.882) (-29.8906, -8.9684) (-29.9867, -9.056) (-30.0583, -9.1226) (-30.1059, -9.1674) (-30.1297, -9.1899) knots 0 0 0 0 0 0.035714 0.071429 0.107143 0.142857 0.178571 0.214286 0.25 0.285714 0.321429 0.357143 0.392857 0.428571 0.464286 0.5 0.535714 0.571429 0.607143 0.642857 0.678571 0.714286 0.75 0.785714 0.821429 0.857143 0.892857 0.928571 0.964286 1 1 1 1 1
  spline S45 degree 4 poles (-29.7771, -10.275) (-29.7447, -10.2792) (-29.6798, -10.2875) (-29.5827, -10.2992) (-29.4535, -10.3136) (-29.3245, -10.3267) (-29.1958, -10.3385) (-29.0672, -10.349) (-28.9389, -10.3581) (-28.8108, -10.3659) (-28.683, -10.3722) (-28.5554, -10.3771) (-28.4282, -10.3806) (-28.3014, -10.3827) (-28.1751, -10.3834) (-28.0492, -10.3826) (-27.9235, -10.3801) (-27.798, -10.3758) (-27.6727, -10.3697) (-27.5477, -10.3618) (-27.4235, -10.3523) (-27.3004, -10.3413) (-27.1786, -10.3288) (-27.0576, -10.3143) (-26.9367, -10.2973) (-26.8151, -10.2769) (-26.6917, -10.2523) (-26.5659, -10.223) (-26.4374, -10.1888) (-26.3389, -10.1593) (-26.2722, -10.1379) (-26.2386, -10.1267) knots 0 0 0 0 0 0.035714 0.071429 0.107143 0.142857 0.178571 0.214286 0.25 0.285714 0.321429 0.357143 0.392857 0.428571 0.464286 0.5 0.535714 0.571429 0.607143 0.642857 0.678571 0.714286 0.75 0.785714 0.821429 0.857143 0.892857 0.928571 0.964286 1 1 1 1 1
  spline S46 degree 4 poles (-25.7142, -11.3928) (-25.7458, -11.4088) (-25.8081, -11.4409) (-25.8986, -11.4898) (-26.0137, -11.5565) (-26.1233, -11.6249) (-26.228, -11.6948) (-26.3285, -11.7665) (-26.426, -11.8399) (-26.5218, -11.9153) (-26.6168, -11.9926) (-26.7117, -12.0718) (-26.8062, -12.1529) (-26.9001, -12.2357) (-26.9931, -12.32) (-27.0849, -12.4057) (-27.1755, -12.4928) (-27.2651, -12.5813) (-27.3539, -12.671) (-27.4421, -12.7621) (-27.5296, -12.8545) (-27.6163, -12.9482) (-27.7022, -13.043) (-27.7873, -13.139) (-27.8715, -13.2362) (-27.955, -13.3344) (-28.0376, -13.4337) (-28.1196, -13.5342) (-28.2008, -13.6356) (-28.2611, -13.7125) (-28.3011, -13.7642) (-28.3211, -13.7901) knots 0 0 0 0 0 0.035714 0.071429 0.107143 0.142857 0.178571 0.214286 0.25 0.285714 0.321429 0.357143 0.392857 0.428571 0.464286 0.5 0.535714 0.571429 0.607143 0.642857 0.678571 0.714286 0.75 0.785714 0.821429 0.857143 0.892857 0.928571 0.964286 1 1 1 1 1
  spline S47 degree 4 poles (-27.8031, -14.8066) (-27.7704, -14.8058) (-27.7051, -14.8038) (-27.6074, -14.8002) (-27.4775, -14.7943) (-27.3481, -14.7871) (-27.2191, -14.7787) (-27.0905, -14.769) (-26.9624, -14.758) (-26.8347, -14.7456) (-26.7074, -14.7319) (-26.5806, -14.7168) (-26.4544, -14.7004) (-26.3289, -14.6827) (-26.204, -14.6636) (-26.0798, -14.6431) (-25.956, -14.621) (-25.8328, -14.5972) (-25.7099, -14.5715) (-25.5877, -14.5441) (-25.4666, -14.5153) (-25.3467, -14.4852) (-25.2283, -14.4537) (-25.111, -14.4205) (-24.9943, -14.3847) (-24.8773, -14.3454) (-24.7593, -14.3018) (-24.6397, -14.2532) (-24.5181, -14.1992) (-24.4254, -14.1545) (-24.3628, -14.1229) (-24.3314, -14.1067) knots 0 0 0 0 0 0.035714 0.071429 0.107143 0.142857 0.178571 0.214286 0.25 0.285714 0.321429 0.357143 0.392857 0.428571 0.464286 0.5 0.535714 0.571429 0.607143 0.642857 0.678571 0.714286 0.75 0.785714 0.821429 0.857143 0.892857 0.928571 0.964286 1 1 1 1 1
  spline S48 degree 4 poles (-23.6154, -15.2751) (-23.6441, -15.2958) (-23.7007, -15.3371) (-23.7825, -15.3995) (-23.8858, -15.4833) (-23.9835, -15.5678) (-24.076, -15.6531) (-24.164, -15.7396) (-24.2489, -15.8273) (-24.3317, -15.9167) (-24.4136, -16.0079) (-24.4948, -16.101) (-24.5755, -16.1959) (-24.6554, -16.2923) (-24.734, -16.3901) (-24.8112, -16.4892) (-24.8871, -16.5894) (-24.9618, -16.6908) (-25.0354, -16.7934) (-25.1082, -16.8972) (-25.1801, -17.0022) (-25.2511, -17.1083) (-25.3211, -17.2154) (-25.3901, -17.3236) (-25.4581, -17.4328) (-25.5251, -17.543) (-25.5912, -17.6541) (-25.6563, -17.7662) (-25.7206, -17.8792) (-25.7681, -17.9647) (-25.7995, -18.022) (-25.8152, -18.0507) knots 0 0 0 0 0 0.035714 0.071429 0.107143 0.142857 0.178571 0.214286 0.25 0.285714 0.321429 0.357143 0.392857 0.428571 0.464286 0.5 0.535714 0.571429 0.607143 0.642857 0.678571 0.714286 0.75 0.785714 0.821429 0.857143 0.892857 0.928571 0.964286 1 1 1 1 1
  spline S49 degree 4 poles (-25.1445, -18.9737) (-25.1124, -18.9677) (-25.0482, -18.9555) (-24.9523, -18.9367) (-24.825, -18.9104) (-24.6983, -18.883) (-24.5722, -18.8545) (-24.4468, -18.8248) (-24.3219, -18.7938) (-24.1977, -18.7616) (-24.0742, -18.7281) (-23.9514, -18.6934) (-23.8293, -18.6574) (-23.7081, -18.6202) (-23.5878, -18.5819) (-23.4683, -18.5421) (-23.3495, -18.5009) (-23.2315, -18.4581) (-23.1142, -18.4136) (-22.9978, -18.3674) (-22.8826, -18.32) (-22.7689, -18.2715) (-22.6569, -18.2219) (-22.5463, -18.1708) (-22.4366, -18.1172) (-22.3272, -18.0602) (-22.2174, -17.9987) (-22.1068, -17.932) (-21.9951, -17.8597) (-21.9104, -17.8012) (-21.8536, -17.7602) (-21.8251, -17.7393) knots 0 0 0 0 0 0.035714 0.071429 0.107143 0.142857 0.178571 0.214286 0.25 0.285714 0.321429 0.357143 0.392857 0.428571 0.464286 0.5 0.535714 0.571429 0.607143 0.642857 0.678571 0.714286 0.75 0.785714 0.821429 0.857143 0.892857 0.928571 0.964286 1 1 1 1 1
  spline S50 degree 4 poles (-20.9351, -18.7813) (-20.9602, -18.8062) (-21.0096, -18.8559) (-21.0808, -18.9304) (-21.1697, -19.0293) (-21.2529, -19.1281) (-21.3309, -19.2269) (-21.4044, -19.326) (-21.4745, -19.4259) (-21.5423, -19.5271) (-21.6089, -19.63) (-21.6746, -19.7347) (-21.7394, -19.841) (-21.8032, -19.9488) (-21.8656, -20.0577) (-21.9263, -20.1675) (-21.9856, -20.2784) (-22.0435, -20.3902) (-22.1002, -20.5031) (-22.1559, -20.617) (-22.2105, -20.7319) (-22.264, -20.8478) (-22.3163, -20.9646) (-22.3675, -21.0823) (-22.4176, -21.2008) (-22.4665, -21.32) (-22.5144, -21.4401) (-22.5612, -21.561) (-22.607, -21.6827) (-22.6406, -21.7745) (-22.6627, -21.836) (-22.6736, -21.8668) knots 0 0 0 0 0 0.035714 0.071429 0.107143 0.142857 0.178571 0.214286 0.25 0.285714 0.321429 0.357143 0.392857 0.428571 0.464286 0.5 0.535714 0.571429 0.607143 0.642857 0.678571 0.714286 0.75 0.785714 0.821429 0.857143 0.892857 0.928571 0.964286 1 1 1 1 1
  spline S51 degree 4 poles (-21.8668, -22.6736) (-21.836, -22.6626) (-21.7746, -22.6404) (-21.6828, -22.6066) (-21.5612, -22.5605) (-21.4403, -22.5135) (-21.3203, -22.4654) (-21.2011, -22.4162) (-21.0827, -22.366) (-20.9651, -22.3146) (-20.8483, -22.2621) (-20.7325, -22.2084) (-20.6176, -22.1537) (-20.5037, -22.098) (-20.3909, -22.0412) (-20.2791, -21.9832) (-20.1682, -21.9239) (-20.0583, -21.8631) (-19.9495, -21.8008) (-19.8417, -21.7371) (-19.7353, -21.6723) (-19.6306, -21.6066) (-19.5277, -21.5402) (-19.4264, -21.4726) (-19.3264, -21.4027) (-19.2272, -21.3294) (-19.1284, -21.2517) (-19.0295, -21.1688) (-18.9305, -21.0802) (-18.856, -21.0093) (-18.8062, -20.9601) (-18.7813, -20.9351) knots 0 0 0 0 0 0.035714 0.071429 0.107143 0.142857 0.178571 0.214286 0.25 0.285714 0.321429 0.357143 0.392857 0.428571 0.464286 0.5 0.535714 0.571429 0.607143 0.642857 0.678571 0.714286 0.75 0.785714 0.821429 0.857143 0.892857 0.928571 0.964286 1 1 1 1 1
  spline S52 degree 4 poles (-17.7393, -21.8251) (-17.7602, -21.8536) (-17.8012, -21.9104) (-17.8598, -21.995) (-17.9322, -22.1066) (-17.9989, -22.2172) (-18.0605, -22.3269) (-18.1176, -22.4363) (-18.1711, -22.546) (-18.2223, -22.6565) (-18.2719, -22.7686) (-18.3204, -22.8822) (-18.3678, -22.9974) (-18.414, -23.1138) (-18.4585, -23.2311) (-18.5014, -23.3491) (-18.5426, -23.4679) (-18.5823, -23.5874) (-18.6206, -23.7078) (-18.6578, -23.829) (-18.6937, -23.9511) (-18.7285, -24.0739) (-18.7619, -24.1975) (-18.7941, -24.3217) (-18.825, -24.4465) (-18.8547, -24.572) (-18.8832, -24.6981) (-18.9105, -24.8248) (-18.9368, -24.9522) (-18.9556, -25.0482) (-18.9677, -25.1124) (-18.9737, -25.1445) knots 0 0 0 0 0 0.035714 0.071429 0.107143 0.142857 0.178571 0.214286 0.25 0.285714 0.321429 0.357143 0.392857 0.428571 0.464286 0.5 0.535714 0.571429 0.607143 0.642857 0.678571 0.714286 0.75 0.785714 0.821429 0.857143 0.892857 0.928571 0.964286 1 1 1 1 1
  spline S53 degree 4 poles (-18.0507, -25.8152) (-18.022, -25.7995) (-17.9647, -25.7681) (-17.8793, -25.7204) (-17.7663, -25.6561) (-17.6543, -25.5908) (-17.5433, -25.5247) (-17.4332, -25.4576) (-17.324, -25.3896) (-17.2159, -25.3205) (-17.1088, -25.2505) (-17.0027, -25.1795) (-16.8977, -25.1075) (-16.7939, -25.0347) (-16.6914, -24.961) (-16.59, -24.8863) (-16.4898, -24.8104) (-16.3908, -24.7332) (-16.293, -24.6545) (-16.1965, -24.5747) (-16.1016, -24.494) (-16.0085, -24.4128) (-15.9173, -24.331) (-15.8278, -24.2482) (-15.74, -24.1634) (-15.6536, -24.0754) (-15.5681, -23.9831) (-15.4835, -23.8855) (-15.3996, -23.7823) (-15.3372, -23.7006) (-15.2958, -23.6441) (-15.2751, -23.6154) knots 0 0 0 0 0 0.035714 0.071429 0.107143 0.142857 0.178571 0.214286 0.25 0.285714 0.321429 0.357143 0.392857 0.428571 0.464286 0.5 0.535714 0.571429 0.607143 0.642857 0.678571 0.714286 0.75 0.785714 0.821429 0.857143 0.892857 0.928571 0.964286 1 1 1 1 1